Autodesk Fusion 360 part; units mm, degrees
(part 11 of 18)
  line L8111 (182.677, -216.38) -> (182.093, -216.4)
  line L8112 (99.4411, -200.179) -> (98.954, -199.84)
  line L8113 (189.133, -201.837) -> (188.753, -201.381)
  line L8114 (85.9088, -203.679) -> (85.6834, -204.229)
  line L8115 (186.561, -215.211) -> (186.044, -215.484)
  line L8116 (88.8893, -200.051) -> (88.417, -200.41)
  line L8117 (103.032, -207.35) -> (103.012, -206.757)
  line L8118 (102.594, -210.117) -> (102.758, -209.547)
  line L8119 (190.719, -205.002) -> (190.544, -204.435)
  line L8120 (101.801, -202.818) -> (101.483, -202.317)
  line L8121 (173.061, -208.139) -> (173.029, -207.555)
  line L8122 (185.918, -199.261) -> (185.373, -199.024)
  line L8123 (190.781, -209.829) -> (190.602, -210.386)
  line L8124 (100.753, -201.381) -> (100.342, -200.952)
  line L8125 (174.402, -202.554) -> (174.727, -202.069)
  line L8126 (190.827, -205.038) -> (190.957, -205.608)
  line L8127 (189.544, -212.463) -> (189.199, -212.934)
  line L8128 (183.835, -216.228) -> (183.258, -216.323)
  line L8129 (190.953, -206.166) -> (190.855, -205.58)
  line L8130 (191.125, -207.524) -> (191.095, -208.107)
  line L8131 (174.888, -212.689) -> (175.257, -213.154)
  line L8132 (85.1587, -206.538) -> (85.1245, -207.131)
  line L8133 (174.108, -203.06) -> (174.402, -202.554)
  line L8134 (184.814, -198.824) -> (184.243, -198.661)
  line L8135 (103.012, -206.757) -> (102.953, -206.166)
  line L8136 (190.855, -205.58) -> (190.719, -205.002)
  line L8137 (181.099, -198.353) -> (181.682, -198.309)
  line L8138 (173.739, -210.617) -> (173.974, -211.163)
  line L8139 (175.084, -201.606) -> (175.469, -201.166)
  line L8140 (88.417, -200.41) -> (87.9695, -200.801)
  line L8141 (101.57, -212.253) -> (101.879, -211.746)
  line L8142 (185.373, -199.024) -> (184.814, -198.824)
  line L8143 (176.783, -200.01) -> (177.268, -199.684)
  line L8144 (173.258, -208.905) -> (173.38, -209.486)
  line L8145 (188.938, -201.449) -> (189.304, -201.904)
  line L8146 (190.14, -211.459) -> (189.858, -211.97)
  line L8147 (86.466, -202.631) -> (86.17, -203.146)
  line L8148 (102.855, -205.58) -> (102.719, -205.002)
  line L8149 (173.277, -205.237) -> (173.432, -204.674)
  line L8150 (187.904, -200.551) -> (187.441, -200.179)
  line L8151 (175.469, -201.166) -> (175.882, -200.753)
  line L8152 (186.044, -215.484) -> (185.511, -215.723)
  line L8153 (186.446, -199.533) -> (185.918, -199.261)
  line L8154 (174.245, -211.691) -> (174.55, -212.201)
  line L8155 (97.9179, -199.261) -> (97.3734, -199.024)
  line L8156 (103.021, -207.787) -> (103.032, -207.35)
  line L8157 (176.643, -214.587) -> (176.187, -214.221)
  line L8158 (102.953, -206.166) -> (102.855, -205.58)
  line L8159 (173.131, -208.719) -> (173.061, -208.139)
  line L8160 (191.012, -206.757) -> (190.953, -206.166)
  line L8161 (177.121, -214.923) -> (176.643, -214.587)
  line L8162 (85.6834, -204.229) -> (85.495, -204.792)
  line L8163 (174.028, -211.487) -> (173.777, -210.959)
  line L8164 (102.544, -204.435) -> (102.332, -203.88)
  line L8165 (87.9695, -200.801) -> (87.5489, -201.22)
  line L8166 (187.673, -200.238) -> (188.121, -200.614)
  line L8167 (188.121, -200.614) -> (188.543, -201.018)
  line L8168 (177.268, -199.684) -> (177.772, -199.389)
  line L8169 (185.128, -198.83) -> (185.671, -199.044)
  line L8170 (180.276, -216.122) -> (180.861, -216.222)
  line L8171 (184.005, -198.508) -> (184.571, -198.651)
  line L8172 (190.391, -210.676) -> (190.594, -210.117)
  line L8173 (174.55, -212.201) -> (174.888, -212.689)
  line L8174 (173.622, -204.122) -> (173.848, -203.583)
  line L8175 (188.543, -201.018) -> (188.938, -201.449)
  line L8176 (186.059, -215.371) -> (186.581, -215.09)
  line L8177 (176.085, -214.005) -> (176.539, -214.387)
  line L8178 (181.509, -216.382) -> (180.927, -216.327)
  line L8179 (92.7068, -198.5) -> (92.1233, -198.611)
  line L8180 (182.093, -216.4) -> (181.509, -216.382)
  line L8181 (188.823, -213.382) -> (188.42, -213.805)
  line L8182 (92.1233, -198.611) -> (91.5484, -198.759)
  line L8183 (188.022, -214.047) -> (188.453, -213.638)
  line L8184 (180.521, -198.435) -> (181.099, -198.353)
  line L8185 (187.059, -214.905) -> (186.561, -215.211)
  line L8186 (182.483, -198.404) -> (181.889, -198.397)
  line L8187 (85.1245, -207.131) -> (85.1297, -207.725)
  line L8188 (185.671, -199.044) -> (186.199, -199.294)
  line L8189 (188.856, -213.201) -> (189.229, -212.739)
  line L8190 (181.889, -198.397) -> (181.296, -198.429)
  line L8191 (94.483, -198.404) -> (93.8893, -198.397)
  line L8192 (190.594, -210.117) -> (190.758, -209.547)
  line L8193 (175.756, -213.827) -> (175.351, -213.406)
  line L8194 (95.6626, -198.537) -> (95.075, -198.451)
  line L8195 (89.3845, -199.723) -> (88.8893, -200.051)
  line L8196 (173.035, -206.971) -> (173.078, -206.388)
  line L8197 (174.727, -202.069) -> (175.084, -201.606)
  line L8198 (100.856, -213.201) -> (101.229, -212.739)
  line L8199 (177.772, -199.389) -> (178.295, -199.128)
  line L8200 (175.882, -200.753) -> (176.32, -200.367)
  line L8201 (189.858, -211.97) -> (189.544, -212.463)
  line L8202 (178.672, -215.735) -> (178.138, -215.498)
  line L8203 (187.536, -214.568) -> (187.059, -214.905)
  line L8204 (185.511, -215.723) -> (184.963, -215.927)
  line L8205 (183.258, -216.323) -> (182.677, -216.38)
  line L8206 (96.8143, -198.824) -> (96.2432, -198.661)
  line L8207 (191.021, -207.787) -> (191.032, -207.35)
  line L8208 (173.562, -210.416) -> (173.382, -209.86)
  line L8209 (174.627, -212.489) -> (174.311, -211.998)
  line L8210 (173.848, -203.583) -> (174.108, -203.06)
  line L8211 (98.4456, -199.533) -> (97.9179, -199.261)
  line L8212 (173.432, -204.674) -> (173.622, -204.122)
  line L8213 (191.051, -206.184) -> (191.108, -206.766)
  line L8214 (102.885, -208.967) -> (102.972, -208.379)
  line L8215 (183.816, -216.134) -> (184.395, -216)
  line L8216 (174.975, -212.959) -> (174.627, -212.489)
  line L8217 (190.389, -210.93) -> (190.14, -211.459)
  line L8218 (99.9045, -200.551) -> (99.4411, -200.179)
  line L8219 (173.033, -207.131) -> (173.035, -206.971)
  line L8220 (99.5654, -214.426) -> (100.022, -214.047)
  line L8221 (97.3734, -199.024) -> (96.8143, -198.824)
  line L8222 (176.32, -200.367) -> (176.783, -200.01)
  line L8223 (86.7955, -202.137) -> (86.466, -202.631)
  line L8224 (173.238, -209.293) -> (173.131, -208.719)
  line L8225 (86.17, -203.146) -> (85.9088, -203.679)
  line L8226 (188.342, -200.952) -> (187.904, -200.551)
  line L8227 (179.22, -215.937) -> (178.672, -215.735)
  line L8228 (187.99, -214.201) -> (187.536, -214.568)
  line L8229 (180.123, -198.611) -> (179.548, -198.759)
  line L8230 (89.9003, -199.429) -> (89.3845, -199.723)
  line L8231 (173.078, -206.388) -> (173.159, -205.81)
  line L8232 (182.639, -216.287) -> (183.23, -216.23)
  line L8233 (190.456, -203.931) -> (190.659, -204.478)
  line L8234 (180.927, -216.327) -> (180.35, -216.234)
  line L8235 (183.23, -216.23) -> (183.816, -216.134)
  line L8236 (191.095, -208.107) -> (191.027, -208.688)
  line L8237 (179.132, -215.807) -> (179.699, -215.983)
  line L8238 (173.38, -209.486) -> (173.541, -210.058)
  line L8239 (101.229, -212.739) -> (101.57, -212.253)
  line L8240 (183.43, -198.402) -> (184.005, -198.508)
  line L8241 (189.879, -211.746) -> (190.153, -211.219)
  line L8242 (190.084, -203.34) -> (189.801, -202.818)
  line L8243 (93.8893, -198.397) -> (93.2963, -198.429)
  line L8244 (176.539, -214.387) -> (177.018, -214.739)
  line L8245 (191.127, -207.35) -> (191.125, -207.524)
  line L8246 (189.483, -202.317) -> (189.133, -201.837)
  line L8247 (184.395, -216) -> (184.963, -215.827)
  line L8248 (175.257, -213.154) -> (175.657, -213.593)
  line L8249 (187.084, -214.774) -> (187.565, -214.426)
  line L8250 (184.963, -215.927) -> (184.404, -216.096)
  line L8251 (90.4345, -199.169) -> (89.9003, -199.429)
  line L8252 (190.972, -208.379) -> (191.021, -207.787)
  line L8253 (190.758, -209.547) -> (190.885, -208.967)
  line L8254 (189.304, -201.904) -> (189.641, -202.381)
  line L8255 (177.9, -199.429) -> (177.385, -199.723)
  line L8256 (173.777, -210.959) -> (173.562, -210.416)
  line L8257 (186.199, -199.294) -> (186.711, -199.576)
  line L8258 (181.682, -198.309) -> (182.266, -198.302)
  line L8259 (183.663, -198.537) -> (183.075, -198.451)
  line L8260 (184.571, -198.651) -> (185.128, -198.83)
  line L8261 (98.954, -199.84) -> (98.4456, -199.533)
  line L8262 (191.027, -208.688) -> (190.922, -209.262)
  line L8263 (189.946, -202.88) -> (190.218, -203.397)
  line L8264 (102.758, -209.547) -> (102.885, -208.967)
  line L8265 (190.153, -211.219) -> (190.391, -210.676)
  line L8266 (177.385, -199.723) -> (176.889, -200.051)
  line L8267 (189.641, -202.381) -> (189.946, -202.88)
  line L8268 (102.084, -203.34) -> (101.801, -202.818)
  line L8269 (187.441, -200.179) -> (186.954, -199.84)
  line L8270 (173.174, -208.317) -> (173.258, -208.905)
  line L8271 (182.85, -198.333) -> (183.43, -198.402)
  line L8272 (189.229, -212.739) -> (189.57, -212.253)
  line L8273 (191.108, -206.766) -> (191.127, -207.35)
  line L8274 (188.753, -201.381) -> (188.342, -200.952)
  line L8275 (90.9847, -198.946) -> (90.4345, -199.169)
  line L8276 (93.2963, -198.429) -> (92.7068, -198.5)
  line L8277 (189.199, -212.934) -> (188.823, -213.382)
  line L8278 (176.187, -214.221) -> (175.756, -213.827)
  line L8279 (179.386, -198.709) -> (179.949, -198.554)
  line L8280 (173.541, -210.058) -> (173.739, -210.617)
  line L8281 (190.885, -208.967) -> (190.972, -208.379)
  line L8282 (186.954, -199.84) -> (186.446, -199.533)
  line L8283 (95.075, -198.451) -> (94.483, -198.404)
  line L8284 (190.659, -204.478) -> (190.827, -205.038)
  line L8285 (102.972, -208.379) -> (103.021, -207.787)
  line L8286 (173.382, -209.86) -> (173.238, -209.293)
  line L8287 (187.203, -199.892) -> (187.673, -200.238)
  line L8288 (179.949, -198.554) -> (180.521, -198.435)
  line L8289 (87.5489, -201.22) -> (87.157, -201.666)
  line L8290 (102.391, -210.676) -> (102.594, -210.117)
  line L8291 (181.452, -216.283) -> (182.046, -216.305)
  line L8292 (102.719, -205.002) -> (102.544, -204.435)
  line L8293 (85.2321, -205.949) -> (85.1587, -206.538)
  line L8294 (101.133, -201.837) -> (100.753, -201.381)
  line L8295 (181.296, -198.429) -> (180.707, -198.5)
  line L8296 (184.243, -198.661) -> (183.663, -198.537)
  line L8297 (179.78, -216.104) -> (179.22, -215.937)
  line L8298 (190.218, -203.397) -> (190.456, -203.931)
  line L8299 (174.311, -211.998) -> (174.028, -211.487)
  line L8300 (177.018, -214.739) -> (177.518, -215.058)
  line L8301 (180.861, -216.222) -> (181.452, -216.283)
  line L8302 (179.548, -198.759) -> (178.985, -198.946)
  line L8303 (180.707, -198.5) -> (180.123, -198.611)
  line L8304 (175.657, -213.593) -> (176.085, -214.005)
  line L8305 (178.434, -199.169) -> (177.9, -199.429)
  line L8306 (176.417, -200.41) -> (175.97, -200.801)
  line L8307 (177.62, -215.227) -> (177.121, -214.923)
  line L8308 (102.153, -211.219) -> (102.391, -210.676)
  line L8309 (185.518, -215.617) -> (186.059, -215.371)
  line L8310 (100.342, -200.952) -> (99.9045, -200.551)
  line L8311 (182.266, -198.302) -> (182.85, -198.333)
  line L8312 (180.35, -216.234) -> (179.78, -216.104)
  line L8313 (176.889, -200.051) -> (176.417, -200.41)
  line L8314 (101.879, -211.746) -> (102.153, -211.219)
  line L8315 (178.039, -215.343) -> (178.578, -215.593)
  line L8316 (173.159, -205.81) -> (173.277, -205.237)
  line L8317 (178.138, -215.498) -> (177.62, -215.227)
  line L8318 (188.42, -213.805) -> (187.99, -214.201)
  line L8319 (173.029, -207.555) -> (173.033, -207.131)
  line L8320 (186.711, -199.576) -> (187.203, -199.892)
  line L8321 (178.985, -198.946) -> (178.434, -199.169)
  line L8322 (183.075, -198.451) -> (182.483, -198.404)
  line L8323 (101.483, -202.317) -> (101.133, -201.837)
  line L8324 (179.699, -215.983) -> (180.276, -216.122)
  line L8325 (91.5484, -198.759) -> (90.9847, -198.946)
  line L8326 (178.834, -198.901) -> (179.386, -198.709)
  line L8327 (184.404, -216.096) -> (183.835, -216.228)
  line L8328 (182.483, -174.704) -> (181.889, -174.697)
  line L8329 (153.549, -201.22) -> (153.157, -201.666)
  line L8330 (151.344, -181.666) -> (151.232, -182.249)
  line L8331 (180.861, -192.522) -> (181.452, -192.583)
  line L8332 (162.395, -192.3) -> (162.963, -192.127)
  line L8333 (187.441, -176.479) -> (186.954, -176.14)
  line L8334 (53.1275, -198.83) -> (53.671, -199.044)
  line L8335 (187.203, -176.192) -> (187.673, -176.538)
  line L8336 (155.385, -199.723) -> (154.889, -200.051)
  line L8337 (175.882, -177.053) -> (176.32, -176.667)
  line L8338 (169.032, -183.65) -> (169.012, -183.057)
  line L8339 (186.711, -175.876) -> (187.203, -176.192)
  line L8340 (164.954, -176.14) -> (164.446, -175.833)
  line L8341 (168.719, -181.302) -> (168.544, -180.735)
  line L8342 (190.855, -181.88) -> (190.719, -181.302)
  line L8343 (176.539, -190.687) -> (177.018, -191.039)
  line L8344 (173.078, -182.688) -> (173.159, -182.11)
  line L8345 (173.061, -184.439) -> (173.029, -183.855)
  line L8346 (169.032, -207.35) -> (169.012, -206.757)
  line L8347 (190.719, -181.302) -> (190.544, -180.735)
  line L8348 (188.823, -189.682) -> (188.42, -190.105)
  line L8349 (191.032, -183.65) -> (191.012, -183.057)
  line L8350 (179.386, -175.009) -> (179.949, -174.854)
  line L8351 (181.889, -174.697) -> (181.296, -174.729)
  line L8352 (188.121, -176.914) -> (188.543, -177.318)
  line L8353 (47.9488, -198.554) -> (48.5208, -198.435)
  line L8354 (156.985, -198.946) -> (156.434, -199.169)
  line L8355 (190.659, -180.778) -> (190.827, -181.338)
  line L8356 (163.373, -175.324) -> (162.814, -175.124)
  line L8357 (112.834, -175.201) -> (113.386, -175.009)
  line L8358 (189.801, -179.118) -> (189.483, -178.617)
  line L8359 (175.469, -177.466) -> (175.882, -177.053)
  line L8360 (154.889, -200.051) -> (154.417, -200.41)
  line L8361 (190.456, -180.231) -> (190.659, -180.778)
  line L8362 (185.918, -175.561) -> (185.373, -175.324)
  line L8363 (123.946, -179.18) -> (124.218, -179.697)
  line L8364 (173.159, -182.11) -> (173.277, -181.537)
  line L8365 (183.43, -174.702) -> (184.005, -174.808)
  line L8366 (42.402, -202.554) -> (42.7274, -202.069)
  line L8367 (168.084, -203.34) -> (167.801, -202.818)
  line L8368 (188.342, -177.252) -> (187.904, -176.851)
  line L8369 (188.022, -190.347) -> (188.453, -189.938)
  line L8370 (183.816, -192.434) -> (184.395, -192.3)
  line L8371 (116.266, -174.602) -> (116.85, -174.633)
  line L8372 (108.727, -178.369) -> (109.084, -177.906)
  line L8373 (121.203, -176.192) -> (121.673, -176.538)
  line L8374 (178.578, -191.893) -> (179.132, -192.107)
  line L8375 (189.229, -189.039) -> (189.57, -188.553)
  line L8376 (152.795, -202.137) -> (152.466, -202.631)
  line L8377 (49.0994, -198.353) -> (49.682, -198.309)
  line L8378 (41.078, -206.388) -> (41.1589, -205.81)
  line L8379 (190.972, -184.679) -> (191.021, -184.087)
  line L8380 (173.258, -185.205) -> (173.38, -185.786)
  line L8381 (177.772, -175.689) -> (178.295, -175.428)
  line L8382 (187.536, -190.868) -> (187.059, -191.205)
  line L8383 (191.021, -184.087) -> (191.032, -183.65)
  line L8384 (180.123, -174.911) -> (179.548, -175.059)
  line L8385 (186.044, -191.784) -> (185.511, -192.023)
  line L8386 (152.466, -178.931) -> (152.17, -179.446)
  line L8387 (173.38, -185.786) -> (173.541, -186.358)
  line L8388 (177.018, -191.039) -> (177.518, -191.358)
  line L8389 (108.402, -178.854) -> (108.727, -178.369)
  line L8390 (182.85, -174.633) -> (183.43, -174.702)
  line L8391 (184.963, -192.227) -> (184.404, -192.396)
  line L8392 (178.138, -191.798) -> (177.62, -191.527)
  line L8393 (184.243, -174.961) -> (183.663, -174.837)
  line L8394 (173.277, -181.537) -> (173.432, -180.974)
  line L8395 (168.758, -209.547) -> (168.885, -208.967)
  line L8396 (154.417, -176.71) -> (153.97, -177.101)
  line L8397 (168.332, -180.18) -> (168.084, -179.64)
  line L8398 (191.027, -184.988) -> (190.922, -185.562)
  line L8399 (53.671, -199.044) -> (54.1995, -199.294)
  line L8400 (189.946, -179.18) -> (190.218, -179.697)
  line L8401 (185.373, -175.324) -> (184.814, -175.124)
  line L8402 (180.927, -192.627) -> (180.35, -192.534)
  line L8403 (109.469, -177.466) -> (109.882, -177.053)
  line L8404 (189.858, -188.27) -> (189.544, -188.763)
  line L8405 (174.627, -188.789) -> (174.311, -188.298)
  line L8406 (152.466, -202.631) -> (152.17, -203.146)
  line L8407 (107.078, -182.688) -> (107.159, -182.11)
  line L8408 (187.059, -191.205) -> (186.561, -191.511)
  line L8409 (173.541, -186.358) -> (173.739, -186.917)
  line L8410 (163.518, -191.917) -> (164.059, -191.671)
  line L8411 (153.97, -177.101) -> (153.549, -177.52)
  line L8412 (167.483, -178.617) -> (167.133, -178.137)
  line L8413 (173.131, -185.019) -> (173.061, -184.439)
  line L8414 (185.511, -192.023) -> (184.963, -192.227)
  line L8415 (52.0047, -198.508) -> (52.5713, -198.651)
  line L8416 (173.848, -179.883) -> (174.108, -179.36)
  line L8417 (151.232, -205.949) -> (151.159, -206.538)
  line L8418 (168.594, -186.417) -> (168.758, -185.847)
  line L8419 (166.753, -177.681) -> (166.342, -177.252)
  line L8420 (188.938, -177.749) -> (189.304, -178.204)
  line L8421 (42.7274, -202.069) -> (43.0836, -201.606)
  line L8422 (163.373, -199.024) -> (162.814, -198.824)
  line L8423 (124.602, -186.686) -> (124.389, -187.23)
  line L8424 (190.957, -181.908) -> (191.051, -182.484)
  line L8425 (165.565, -190.726) -> (166.022, -190.347)
  line L8426 (173.909, -179.979) -> (173.683, -180.529)
  line L8427 (123.304, -178.204) -> (123.641, -178.681)
  line L8428 (179.132, -192.107) -> (179.699, -192.283)
  line L8429 (164.059, -191.671) -> (164.581, -191.39)
  line L8430 (174.245, -187.991) -> (174.55, -188.501)
  line L8431 (189.483, -178.617) -> (189.133, -178.137)
  line L8432 (180.35, -192.534) -> (179.78, -192.404)
  line L8433 (153.157, -201.666) -> (152.795, -202.137)
  line L8434 (45.7724, -199.389) -> (46.2951, -199.128)
  line L8435 (46.8336, -198.901) -> (47.3856, -198.709)
  line L8436 (191.051, -182.484) -> (191.108, -183.066)
  line L8437 (111.268, -175.984) -> (111.772, -175.689)
  line L8438 (158.276, -192.422) -> (158.861, -192.522)
  line L8439 (122.543, -177.318) -> (122.938, -177.749)
  line L8440 (124.659, -180.778) -> (124.827, -181.338)
  line L8441 (188.753, -177.681) -> (188.342, -177.252)
  line L8442 (168.391, -186.976) -> (168.594, -186.417)
  line L8443 (151.909, -203.679) -> (151.683, -204.229)
  line L8444 (159.452, -192.583) -> (160.046, -192.605)
  line L8445 (168.972, -184.679) -> (169.021, -184.087)
  line L8446 (152.795, -178.437) -> (152.466, -178.931)
  line L8447 (180.521, -174.735) -> (181.099, -174.653)
  line L8448 (190.885, -185.267) -> (190.972, -184.679)
  line L8449 (173.035, -183.271) -> (173.078, -182.688)
  line L8450 (189.544, -188.763) -> (189.199, -189.234)
  line L8451 (181.296, -174.729) -> (180.707, -174.8)
  line L8452 (151.124, -183.431) -> (151.13, -184.025)
  line L8453 (114.521, -174.735) -> (115.099, -174.653)
  line L8454 (184.005, -174.808) -> (184.571, -174.951)
  line L8455 (182.639, -192.587) -> (183.23, -192.53)
  line L8456 (41.8482, -203.583) -> (42.1085, -203.06)
  line L8457 (156.985, -175.246) -> (156.434, -175.469)
  line L8458 (167.483, -202.317) -> (167.133, -201.837)
  line L8459 (174.311, -188.298) -> (174.028, -187.787)
  line L8460 (179.78, -192.404) -> (179.22, -192.237)
  line L8461 (41.2769, -205.237) -> (41.4315, -204.674)
  line L8462 (173.238, -185.593) -> (173.131, -185.019)
  line L8463 (173.13, -184.025) -> (173.174, -184.617)
  line L8464 (177.518, -191.358) -> (178.039, -191.643)
  line L8465 (190.781, -186.129) -> (190.602, -186.686)
  line L8466 (168.544, -180.735) -> (168.332, -180.18)
  line L8467 (50.8498, -198.333) -> (51.4301, -198.402)
  line L8468 (124.957, -181.908) -> (125.051, -182.484)
  line L8469 (109.084, -177.906) -> (109.469, -177.466)
  line L8470 (113.386, -175.009) -> (113.949, -174.854)
  line L8471 (165.904, -200.551) -> (165.441, -200.179)
  line L8472 (168.855, -181.88) -> (168.719, -181.302)
  line L8473 (179.548, -175.059) -> (178.985, -175.246)
  line L8474 (122.121, -176.914) -> (122.543, -177.318)
  line L8475 (43.8816, -200.753) -> (44.3203, -200.367)
  line L8476 (124.218, -179.697) -> (124.456, -180.231)
  line L8477 (159.889, -198.397) -> (159.296, -198.429)
  line L8478 (156.578, -191.893) -> (157.132, -192.107)
  line L8479 (188.42, -190.105) -> (187.99, -190.501)
  line L8480 (151.13, -207.725) -> (151.174, -208.317)
  line L8481 (163.918, -175.561) -> (163.373, -175.324)
  line L8482 (174.975, -189.259) -> (174.627, -188.789)
  line L8483 (118.571, -174.951) -> (119.128, -175.13)
  line L8484 (156.434, -175.469) -> (155.9, -175.729)
  line L8485 (124.781, -186.129) -> (124.602, -186.686)
  line L8486 (159.296, -198.429) -> (158.707, -198.5)
  line L8487 (189.199, -189.234) -> (188.823, -189.682)
  line L8488 (119.128, -175.13) -> (119.671, -175.344)
  line L8489 (175.351, -189.706) -> (174.975, -189.259)
  line L8490 (151.159, -206.538) -> (151.124, -207.131)
  line L8491 (173.382, -186.16) -> (173.238, -185.593)
  line L8492 (173.344, -181.666) -> (173.232, -182.249)
  line L8493 (174.888, -188.989) -> (175.257, -189.454)
  line L8494 (125.095, -184.407) -> (125.027, -184.988)
  line L8495 (167.229, -189.039) -> (167.57, -188.553)
  line L8496 (44.3203, -200.367) -> (44.7829, -200.01)
  line L8497 (168.084, -179.64) -> (167.801, -179.118)
  line L8498 (165.084, -191.074) -> (165.565, -190.726)
  line L8499 (158.123, -198.611) -> (157.548, -198.759)
  line L8500 (178.434, -175.469) -> (177.9, -175.729)
  line L8501 (169.021, -207.787) -> (169.032, -207.35)
  line L8502 (108.108, -179.36) -> (108.402, -178.854)
  line L8503 (168.953, -182.466) -> (168.855, -181.88)
  line L8504 (120.711, -175.876) -> (121.203, -176.192)
  line L8505 (190.594, -186.417) -> (190.758, -185.847)
  line L8506 (165.441, -176.479) -> (164.954, -176.14)
  line L8507 (112.295, -175.428) -> (112.834, -175.201)
  line L8508 (179.949, -174.854) -> (180.521, -174.735)
  line L8509 (155.385, -176.023) -> (154.889, -176.351)
  line L8510 (191.012, -183.057) -> (190.953, -182.466)
  line L8511 (42.1085, -203.06) -> (42.402, -202.554)
  line L8512 (158.123, -174.911) -> (157.548, -175.059)
  line L8513 (157.548, -198.759) -> (156.985, -198.946)
  line L8514 (107.432, -180.974) -> (107.622, -180.422)
  line L8515 (185.128, -175.13) -> (185.671, -175.344)
  line L8516 (173.974, -187.463) -> (174.245, -187.991)
  line L8517 (41.6223, -204.122) -> (41.8482, -203.583)
  line L8518 (189.133, -178.137) -> (188.753, -177.681)
  line L8519 (125.027, -184.988) -> (124.922, -185.562)
  line L8520 (179.22, -192.237) -> (178.672, -192.035)
  line L8521 (161.075, -198.451) -> (160.483, -198.404)
  line L8522 (190.389, -187.23) -> (190.14, -187.759)
  line L8523 (188.543, -177.318) -> (188.938, -177.749)
  line L8524 (187.084, -191.074) -> (187.565, -190.726)
  line L8525 (151.683, -180.529) -> (151.495, -181.092)
  line L8526 (153.549, -177.52) -> (153.157, -177.966)
  line L8527 (184.404, -192.396) -> (183.835, -192.528)
  line L8528 (186.199, -175.594) -> (186.711, -175.876)
  line L8529 (159.296, -174.729) -> (158.707, -174.8)
  line L8530 (184.963, -192.127) -> (185.518, -191.917)
  line L8531 (166.342, -177.252) -> (165.904, -176.851)
  line L8532 (155.9, -175.729) -> (155.385, -176.023)
  line L8533 (174.795, -178.437) -> (174.466, -178.931)
  line L8534 (187.565, -190.726) -> (188.022, -190.347)
  line L8535 (153.97, -200.801) -> (153.549, -201.22)
  line L8536 (167.133, -178.137) -> (166.753, -177.681)
  line L8537 (41.1589, -205.81) -> (41.2769, -205.237)
  line L8538 (191.095, -184.407) -> (191.027, -184.988)
  line L8539 (125.051, -182.484) -> (125.108, -183.066)
  line L8540 (175.549, -177.52) -> (175.157, -177.966)
  line L8541 (161.816, -192.434) -> (162.395, -192.3)
  line L8542 (161.663, -174.837) -> (161.075, -174.751)
  line L8543 (151.683, -204.229) -> (151.495, -204.792)
  line L8544 (113.949, -174.854) -> (114.521, -174.735)
  line L8545 (162.243, -174.961) -> (161.663, -174.837)
  line L8546 (177.268, -175.984) -> (177.772, -175.689)
  line L8547 (173.683, -180.529) -> (173.495, -181.092)
  line L8548 (185.518, -191.917) -> (186.059, -191.671)
  line L8549 (107.622, -180.422) -> (107.848, -179.883)
  line L8550 (176.085, -190.305) -> (176.539, -190.687)
  line L8551 (167.133, -201.837) -> (166.753, -201.381)
  line L8552 (125.127, -183.65) -> (125.125, -183.824)
  line L8553 (52.5713, -198.651) -> (53.1275, -198.83)
  line L8554 (120.199, -175.594) -> (120.711, -175.876)
  line L8555 (125.108, -183.066) -> (125.127, -183.65)
  line L8556 (51.4301, -198.402) -> (52.0047, -198.508)
  line L8557 (175.756, -190.127) -> (175.351, -189.706)
  line L8558 (168.885, -185.267) -> (168.972, -184.679)
  line L8559 (166.856, -189.501) -> (167.229, -189.039)
  line L8560 (181.682, -174.609) -> (182.266, -174.602)
  line L8561 (124.389, -187.23) -> (124.14, -187.759)
  line L8562 (181.099, -174.653) -> (181.682, -174.609)
  line L8563 (186.059, -191.671) -> (186.581, -191.39)
  line L8564 (178.039, -191.643) -> (178.578, -191.893)
  line L8565 (184.571, -174.951) -> (185.128, -175.13)
  line L8566 (161.23, -192.53) -> (161.816, -192.434)
  line L8567 (167.801, -179.118) -> (167.483, -178.617)
  line L8568 (165.441, -200.179) -> (164.954, -199.84)
  line L8569 (169.021, -184.087) -> (169.032, -183.65)
  line L8570 (189.641, -178.681) -> (189.946, -179.18)
  line L8571 (123.641, -178.681) -> (123.946, -179.18)
  line L8572 (160.483, -174.704) -> (159.889, -174.697)
  line L8573 (168.544, -204.435) -> (168.332, -203.88)
  line L8574 (166.453, -189.938) -> (166.856, -189.501)
  line L8575 (163.918, -199.261) -> (163.373, -199.024)
  line L8576 (166.753, -201.381) -> (166.342, -200.952)
  line L8577 (190.922, -185.562) -> (190.781, -186.129)
  line L8578 (159.889, -174.697) -> (159.296, -174.729)
  line L8579 (190.758, -185.847) -> (190.885, -185.267)
  line L8580 (151.495, -181.092) -> (151.344, -181.666)
  line L8581 (176.643, -190.887) -> (176.187, -190.521)
  line L8582 (124.827, -181.338) -> (124.957, -181.908)
  line L8583 (177.9, -175.729) -> (177.385, -176.023)
  line L8584 (173.033, -183.431) -> (173.035, -183.271)
  line L8585 (174.466, -178.931) -> (174.17, -179.446)
  line L8586 (175.97, -177.101) -> (175.549, -177.52)
  line L8587 (155.9, -199.429) -> (155.385, -199.723)
  line L8588 (151.909, -179.979) -> (151.683, -180.529)
  line L8589 (168.855, -205.58) -> (168.719, -205.002)
  line L8590 (183.835, -192.528) -> (183.258, -192.623)
  line L8591 (177.385, -176.023) -> (176.889, -176.351)
  line L8592 (153.157, -177.966) -> (152.795, -178.437)
  line L8593 (190.332, -180.18) -> (190.084, -179.64)
  line L8594 (158.861, -192.522) -> (159.452, -192.583)
  line L8595 (119.671, -175.344) -> (120.199, -175.594)
  line L8596 (175.657, -189.893) -> (176.085, -190.305)
  line L8597 (176.187, -190.521) -> (175.756, -190.127)
  line L8598 (116.85, -174.633) -> (117.43, -174.702)
  line L8599 (111.772, -175.689) -> (112.295, -175.428)
  line L8600 (178.295, -175.428) -> (178.834, -175.201)
  line L8601 (174.402, -178.854) -> (174.727, -178.369)
  line L8602 (168.953, -206.166) -> (168.855, -205.58)
  line L8603 (115.682, -174.609) -> (116.266, -174.602)
  line L8604 (173.622, -180.422) -> (173.848, -179.883)
  line L8605 (152.17, -179.446) -> (151.909, -179.979)
  line L8606 (107.159, -182.11) -> (107.277, -181.537)
  line L8607 (110.32, -176.667) -> (110.783, -176.31)
  line L8608 (190.602, -186.686) -> (190.389, -187.23)
  line L8609 (174.028, -187.787) -> (173.777, -187.259)
  line L8610 (49.682, -198.309) -> (50.2663, -198.302)
  line L8611 (182.677, -192.68) -> (182.093, -192.7)
  line L8612 (151.344, -205.366) -> (151.232, -205.949)
  line L8613 (175.157, -177.966) -> (174.795, -178.437)
  line L8614 (178.834, -175.201) -> (179.386, -175.009)
  line L8615 (186.561, -191.511) -> (186.044, -191.784)
  line L8616 (164.954, -199.84) -> (164.446, -199.533)
  line L8617 (157.132, -192.107) -> (157.699, -192.283)
  line L8618 (167.879, -188.046) -> (168.153, -187.519)
  line L8619 (191.108, -183.066) -> (191.127, -183.65)
  line L8620 (176.32, -176.667) -> (176.783, -176.31)
  line L8621 (180.707, -174.8) -> (180.123, -174.911)
  line L8622 (162.814, -175.124) -> (162.243, -174.961)
  line L8623 (162.243, -198.661) -> (161.663, -198.537)
  line L8624 (173.562, -186.716) -> (173.382, -186.16)
  line L8625 (190.084, -179.64) -> (189.801, -179.118)
  line L8626 (184.395, -192.3) -> (184.963, -192.127)
  line L8627 (117.43, -174.702) -> (118.005, -174.808)
  line L8628 (187.904, -176.851) -> (187.441, -176.479)
  line L8629 (161.075, -174.751) -> (160.483, -174.704)
  line L8630 (189.879, -188.046) -> (190.153, -187.519)
  line L8631 (154.889, -176.351) -> (154.417, -176.71)
  line L8632 (190.544, -180.735) -> (190.332, -180.18)
  line L8633 (177.62, -191.527) -> (177.121, -191.223)
  line L8634 (184.814, -175.124) -> (184.243, -174.961)
  line L8635 (167.801, -202.818) -> (167.483, -202.317)
  line L8636 (173.777, -187.259) -> (173.562, -186.716)
  line L8637 (168.885, -208.967) -> (168.972, -208.379)
  line L8638 (152.17, -203.146) -> (151.909, -203.679)
  line L8639 (168.153, -187.519) -> (168.391, -186.976)
  line L8640 (167.57, -188.553) -> (167.879, -188.046)
  line L8641 (188.453, -189.938) -> (188.856, -189.501)
  line L8642 (166.342, -200.952) -> (165.904, -200.551)
  line L8643 (156.039, -191.643) -> (156.578, -191.893)
  line L8644 (115.099, -174.653) -> (115.682, -174.609)
  line L8645 (185.671, -175.344) -> (186.199, -175.594)
  line L8646 (173.174, -184.617) -> (173.258, -185.205)
  line L8647 (187.673, -176.538) -> (188.121, -176.914)
  line L8648 (173.739, -186.917) -> (173.974, -187.463)
  line L8649 (156.434, -199.169) -> (155.9, -199.429)
  line L8650 (44.7829, -200.01) -> (45.2676, -199.684)
  line L8651 (173.495, -181.092) -> (173.344, -181.666)
  line L8652 (158.707, -174.8) -> (158.123, -174.911)
  line L8653 (178.672, -192.035) -> (178.138, -191.798)
  line L8654 (151.495, -204.792) -> (151.344, -205.366)
  line L8655 (173.159, -182.838) -> (173.124, -183.431)
  line L8656 (173.232, -182.249) -> (173.159, -182.838)
  line L8657 (188.856, -189.501) -> (189.229, -189.039)
  line L8658 (124.456, -180.231) -> (124.659, -180.778)
  line L8659 (47.3856, -198.709) -> (47.9488, -198.554)
  line L8660 (160.639, -192.587) -> (161.23, -192.53)
  line L8661 (158.707, -198.5) -> (158.123, -198.611)
  line L8662 (50.2663, -198.302) -> (50.8498, -198.333)
  line L8663 (177.121, -191.223) -> (176.643, -190.887)
  line L8664 (182.093, -192.7) -> (181.509, -192.682)
  line L8665 (151.232, -182.249) -> (151.159, -182.838)
  line L8666 (118.005, -174.808) -> (118.571, -174.951)
  line L8667 (151.124, -207.131) -> (151.13, -207.725)
  line L8668 (183.075, -174.751) -> (182.483, -174.704)
  line L8669 (190.14, -187.759) -> (189.858, -188.27)
  line L8670 (178.985, -175.246) -> (178.434, -175.469)
  line L8671 (183.23, -192.53) -> (183.816, -192.434)
  line L8672 (157.548, -175.059) -> (156.985, -175.246)
  line L8673 (54.1995, -199.294) -> (54.7108, -199.576)
  line L8674 (179.699, -192.283) -> (180.276, -192.422)
  line L8675 (180.276, -192.422) -> (180.861, -192.522)
  line L8676 (183.258, -192.623) -> (182.677, -192.68)
  line L8677 (186.581, -191.39) -> (187.084, -191.074)
  line L8678 (176.889, -176.351) -> (176.417, -176.71)
  line L8679 (168.719, -205.002) -> (168.544, -204.435)
  line L8680 (169.012, -183.057) -> (168.953, -182.466)
  line L8681 (181.509, -192.682) -> (180.927, -192.627)
  line L8682 (168.758, -185.847) -> (168.885, -185.267)
  line L8683 (176.783, -176.31) -> (177.268, -175.984)
  line L8684 (187.99, -190.501) -> (187.536, -190.868)
  line L8685 (181.452, -192.583) -> (182.046, -192.605)
  line L8686 (191.125, -183.824) -> (191.095, -184.407)
  line L8687 (175.257, -189.454) -> (175.657, -189.893)
  line L8688 (165.904, -176.851) -> (165.441, -176.479)
  line L8689 (45.2676, -199.684) -> (45.7724, -199.389)
  line L8690 (173.029, -183.855) -> (173.033, -183.431)
  line L8691 (166.022, -190.347) -> (166.453, -189.938)
  line L8692 (154.417, -200.41) -> (153.97, -200.801)
  line L8693 (162.963, -192.127) -> (163.518, -191.917)
  line L8694 (164.446, -199.533) -> (163.918, -199.261)
  line L8695 (162.814, -198.824) -> (162.243, -198.661)
  line L8696 (109.882, -177.053) -> (110.32, -176.667)
  line L8697 (175.084, -177.906) -> (175.469, -177.466)
  line L8698 (174.108, -179.36) -> (174.402, -178.854)
  line L8699 (164.446, -175.833) -> (163.918, -175.561)
  line L8700 (182.046, -192.605) -> (182.639, -192.587)
  line L8701 (164.581, -191.39) -> (165.084, -191.074)
  line L8702 (160.483, -198.404) -> (159.889, -198.397)
  line L8703 (107.848, -179.883) -> (108.108, -179.36)
  line L8704 (151.159, -182.838) -> (151.124, -183.431)
  line L8705 (121.673, -176.538) -> (122.121, -176.914)
  line L8706 (190.153, -187.519) -> (190.391, -186.976)
  line L8707 (110.783, -176.31) -> (111.268, -175.984)
  line L8708 (176.417, -176.71) -> (175.97, -177.101)
  line L8709 (189.57, -188.553) -> (189.879, -188.046)
  line L8710 (48.5208, -198.435) -> (49.0994, -198.353)
  line L8711 (190.827, -181.338) -> (190.957, -181.908)
  line L8712 (182.266, -174.602) -> (182.85, -174.633)
  line L8713 (41.4315, -204.674) -> (41.6223, -204.122)
  line L8714 (191.127, -183.65) -> (191.125, -183.824)
  line L8715 (46.2951, -199.128) -> (46.8336, -198.901)
  line L8716 (160.046, -192.605) -> (160.639, -192.587)
  line L8717 (168.972, -208.379) -> (169.021, -207.787)
  line L8718 (173.432, -180.974) -> (173.622, -180.422)
  line L8719 (157.699, -192.283) -> (158.276, -192.422)
  line L8720 (186.446, -175.833) -> (185.918, -175.561)
  line L8721 (189.304, -178.204) -> (189.641, -178.681)
  line L8722 (168.332, -203.88) -> (168.084, -203.34)
  line L8723 (190.391, -186.976) -> (190.594, -186.417)
  line L8724 (151.13, -184.025) -> (151.174, -184.617)
  line L8725 (190.953, -182.466) -> (190.855, -181.88)
  line L8726 (183.663, -174.837) -> (183.075, -174.751)
  line L8727 (169.012, -206.757) -> (168.953, -206.166)
  line L8728 (173.124, -183.431) -> (173.13, -184.025)
  line L8729 (124.922, -185.562) -> (124.781, -186.129)
  line L8730 (174.17, -179.446) -> (173.909, -179.979)
  line L8731 (186.954, -176.14) -> (186.446, -175.833)
  line L8732 (174.55, -188.501) -> (174.888, -188.989)
  line L8733 (54.7108, -199.576) -> (55.2028, -199.892)
  line L8734 (122.938, -177.749) -> (123.304, -178.204)
  line L8735 (43.4688, -201.166) -> (43.8816, -200.753)
  line L8736 (161.663, -198.537) -> (161.075, -198.451)
  line L8737 (43.0836, -201.606) -> (43.4688, -201.166)
  line L8738 (107.277, -181.537) -> (107.432, -180.974)
  line L8739 (190.218, -179.697) -> (190.456, -180.231)
  line L8740 (174.727, -178.369) -> (175.084, -177.906)
  line L8741 (125.125, -183.824) -> (125.095, -184.407)
  line L8742 (36.9224, -209.262) -> (36.7806, -209.829)
  line L8743 (44.1873, -214.221) -> (43.7561, -213.827)
  line L8744 (19.9741, -211.163) -> (20.2446, -211.691)
  line L8745 (32.954, -199.84) -> (32.4456, -199.533)
  line L8746 (43.7561, -213.827) -> (43.3513, -213.406)
  line L8747 (45.6204, -215.227) -> (45.1214, -214.923)
  line L8748 (45.9003, -199.429) -> (45.3845, -199.723)
  line L8749 (54.5813, -215.09) -> (55.0844, -214.774)
  line L8750 (50.0455, -216.305) -> (50.6391, -216.287)
  line L8751 (20.0276, -211.487) -> (19.7774, -210.959)
  line L8752 (26.7068, -198.5) -> (26.1233, -198.611)
  line L8753 (123.946, -202.88) -> (124.218, -203.397)
  line L8754 (107.078, -206.388) -> (107.159, -205.81)
  line L8755 (27.0994, -198.353) -> (27.682, -198.309)
  line L8756 (56.9379, -201.449) -> (57.3045, -201.904)
  line L8757 (22.0847, -214.005) -> (22.539, -214.387)
  line L8758 (36.6024, -210.386) -> (36.3887, -210.93)
  line L8759 (119.671, -199.044) -> (120.199, -199.294)
  line L8760 (57.3045, -201.904) -> (57.6409, -202.381)
  line L8761 (46.4345, -199.169) -> (45.9003, -199.429)
  line L8762 (59.1268, -207.35) -> (59.1251, -207.524)
  line L8763 (47.2202, -215.937) -> (46.672, -215.735)
  line L8764 (115.099, -198.353) -> (115.682, -198.309)
  line L8765 (21.6569, -213.593) -> (22.0847, -214.005)
  line L8766 (36.4559, -203.931) -> (36.6591, -204.478)
  line L8767 (25.3856, -198.709) -> (25.9488, -198.554)
  line L8768 (47.6987, -215.983) -> (48.2761, -216.122)
  line L8769 (107.622, -204.122) -> (107.848, -203.583)
  line L8770 (53.5182, -215.617) -> (54.0585, -215.371)
  line L8771 (41.3817, -209.86) -> (41.2379, -209.293)
  line L8772 (36.9531, -206.166) -> (36.8551, -205.58)
  line L8773 (19.2769, -205.237) -> (19.4315, -204.674)
  line L8774 (19.1297, -207.725) -> (19.1742, -208.317)
  line L8775 (48.2761, -216.122) -> (48.8615, -216.222)
  line L8776 (36.9725, -208.379) -> (37.0211, -207.787)
  line L8777 (37.0318, -207.35) -> (37.0121, -206.757)
  line L8778 (32.0441, -215.484) -> (31.5109, -215.723)
  line L8779 (20.6274, -212.489) -> (20.3113, -211.998)
  line L8780 (28.6766, -216.38) -> (28.0926, -216.4)
  line L8781 (125.051, -206.184) -> (125.108, -206.766)
  line L8782 (115.682, -198.309) -> (116.266, -198.302)
  line L8783 (34.42, -213.805) -> (33.9903, -214.201)
  line L8784 (48.7068, -198.5) -> (48.1233, -198.611)
  line L8785 (55.2028, -199.892) -> (55.6734, -200.238)
  line L8786 (35.3045, -201.904) -> (35.6409, -202.381)
  line L8787 (36.3914, -210.676) -> (36.5935, -210.117)
  line L8788 (57.4833, -202.317) -> (57.1334, -201.837)
  line L8789 (20.7955, -202.137) -> (20.466, -202.631)
  line L8790 (32.4456, -199.533) -> (31.9179, -199.261)
  line L8791 (58.1404, -211.459) -> (57.8585, -211.97)
  line L8792 (30.9627, -215.827) -> (31.5182, -215.617)
  line L8793 (51.075, -198.451) -> (50.483, -198.404)
  line L8794 (37.0211, -207.787) -> (37.0318, -207.35)
  line L8795 (36.1404, -211.459) -> (35.8585, -211.97)
  line L8796 (41.1245, -207.131) -> (41.1297, -207.725)
  line L8797 (34.453, -213.638) -> (34.8557, -213.201)
  line L8798 (122.121, -200.614) -> (122.543, -201.018)
  line L8799 (28.2663, -198.302) -> (28.8498, -198.333)
  line L8800 (59.0274, -208.688) -> (58.9224, -209.262)
  line L8801 (25.6987, -215.983) -> (26.2761, -216.122)
  line L8802 (108.727, -202.069) -> (109.084, -201.606)
  line L8803 (41.1587, -206.538) -> (41.1245, -207.131)
  line L8804 (48.8615, -216.222) -> (49.4521, -216.283)
  line L8805 (59.0121, -206.757) -> (58.9531, -206.166)
  line L8806 (48.35, -216.234) -> (47.7803, -216.104)
  line L8807 (31.5109, -215.723) -> (30.9634, -215.927)
  line L8808 (107.159, -205.81) -> (107.277, -205.237)
  line L8809 (41.2578, -208.905) -> (41.3803, -209.486)
  line L8810 (34.0223, -214.047) -> (34.453, -213.638)
  line L8811 (19.6222, -204.122) -> (19.8482, -203.583)
  line L8812 (41.495, -204.792) -> (41.3443, -205.366)
  line L8813 (42.8876, -212.689) -> (43.2572, -213.154)
  line L8814 (58.8551, -205.58) -> (58.7185, -205.002)
  line L8815 (43.5489, -201.22) -> (43.157, -201.666)
  line L8816 (21.2572, -213.154) -> (21.6569, -213.593)
  line L8817 (41.1742, -208.317) -> (41.2578, -208.905)
  line L8818 (59.0951, -208.107) -> (59.0274, -208.688)
  line L8819 (20.9746, -212.959) -> (20.6274, -212.489)
  line L8820 (19.4315, -204.674) -> (19.6222, -204.122)
  line L8821 (42.3113, -211.998) -> (42.0276, -211.487)
  line L8822 (117.43, -198.402) -> (118.005, -198.508)
  line L8823 (47.7803, -216.104) -> (47.2202, -215.937)
  line L8824 (35.8006, -202.818) -> (35.4833, -202.317)
  line L8825 (27.682, -198.309) -> (28.2663, -198.302)
  line L8826 (122.938, -201.449) -> (123.304, -201.904)
  line L8827 (41.9088, -203.679) -> (41.6834, -204.229)
  line L8828 (46.5778, -215.593) -> (47.1318, -215.807)
  line L8829 (111.772, -199.389) -> (112.295, -199.128)
  line L8830 (25.5484, -198.759) -> (24.9847, -198.946)
  line L8831 (29.075, -198.451) -> (28.483, -198.404)
  line L8832 (45.3845, -199.723) -> (44.8893, -200.051)
  line L8833 (19.2578, -208.905) -> (19.3803, -209.486)
  line L8834 (37.1251, -207.524) -> (37.0951, -208.107)
  line L8835 (116.266, -198.302) -> (116.85, -198.333)
  line L8836 (27.5085, -216.382) -> (26.9269, -216.327)
  line L8837 (42.6274, -212.489) -> (42.3113, -211.998)
  line L8838 (52.2432, -198.661) -> (51.6626, -198.537)
  line L8839 (33.9903, -214.201) -> (33.5358, -214.568)
  line L8840 (21.5489, -201.22) -> (21.157, -201.666)
  line L8841 (56.42, -213.805) -> (55.9903, -214.201)
  line L8842 (19.3443, -205.366) -> (19.232, -205.949)
  line L8843 (33.0844, -214.774) -> (33.5654, -214.426)
  line L8844 (58.9531, -206.166) -> (58.8551, -205.58)
  line L8845 (25.2202, -215.937) -> (24.672, -215.735)
  line L8846 (43.9695, -200.801) -> (43.5489, -201.22)
  line L8847 (59.0318, -207.35) -> (59.0121, -206.757)
  line L8848 (41.1297, -207.725) -> (41.1742, -208.317)
  line L8849 (24.4345, -199.169) -> (23.9003, -199.429)
  line L8850 (44.8893, -200.051) -> (44.417, -200.41)
  line L8851 (55.4411, -200.179) -> (54.954, -199.84)
  line L8852 (23.1214, -214.923) -> (22.643, -214.587)
  line L8853 (58.9575, -205.608) -> (59.0514, -206.184)
  line L8854 (57.5441, -212.463) -> (57.1986, -212.934)
  line L8855 (58.084, -203.34) -> (57.8006, -202.818)
  line L8856 (56.3423, -200.952) -> (55.9045, -200.551)
  line L8857 (31.5182, -215.617) -> (32.0585, -215.371)
  line L8858 (57.9457, -202.88) -> (58.2178, -203.397)
  line L8859 (46.138, -215.498) -> (45.6204, -215.227)
  line L8860 (36.8551, -205.58) -> (36.7185, -205.002)
  line L8861 (55.0587, -214.905) -> (54.5607, -215.211)
  line L8862 (45.5183, -215.058) -> (46.0392, -215.343)
  line L8863 (19.0347, -206.971) -> (19.078, -206.388)
  line L8864 (41.2321, -205.949) -> (41.1587, -206.538)
  line L8865 (19.0332, -207.131) -> (19.0347, -206.971)
  line L8866 (124.456, -203.931) -> (124.659, -204.478)
  line L8867 (34.9379, -201.449) -> (35.3045, -201.904)
  line L8868 (43.157, -201.666) -> (42.7955, -202.137)
  line L8869 (23.3845, -199.723) -> (22.8893, -200.051)
  line L8870 (58.7806, -209.829) -> (58.6024, -210.386)
  line L8871 (42.9746, -212.959) -> (42.6274, -212.489)
  line L8872 (54.4456, -199.533) -> (53.9179, -199.261)
  line L8873 (37.0121, -206.757) -> (36.9531, -206.166)
  line L8874 (32.5607, -215.211) -> (32.0441, -215.484)
  line L8875 (28.8498, -198.333) -> (29.4301, -198.402)
  line L8876 (28.483, -198.404) -> (27.8893, -198.397)
  line L8877 (59.0211, -207.787) -> (59.0318, -207.35)
  line L8878 (30.4039, -216.096) -> (29.8346, -216.228)
  line L8879 (52.8143, -198.824) -> (52.2432, -198.661)
  line L8880 (41.0347, -206.971) -> (41.078, -206.388)
  line L8881 (52.9634, -215.927) -> (52.4039, -216.096)
  line L8882 (48.9269, -216.327) -> (48.35, -216.234)
  line L8883 (26.2761, -216.122) -> (26.8615, -216.222)
  line L8884 (108.402, -202.554) -> (108.727, -202.069)
  line L8885 (41.1309, -208.719) -> (41.0612, -208.139)
  line L8886 (57.8785, -211.746) -> (58.1527, -211.219)
  line L8887 (20.3113, -211.998) -> (20.0276, -211.487)
  line L8888 (57.2286, -212.739) -> (57.57, -212.253)
  line L8889 (57.6409, -202.381) -> (57.9457, -202.88)
  line L8890 (22.1873, -214.221) -> (21.7561, -213.827)
  line L8891 (55.6734, -200.238) -> (56.1207, -200.614)
  line L8892 (50.6766, -216.38) -> (50.0926, -216.4)
  line L8893 (21.157, -201.666) -> (20.7955, -202.137)
  line L8894 (58.1527, -211.219) -> (58.3914, -210.676)
  line L8895 (124.827, -205.038) -> (124.957, -205.608)
  line L8896 (37.1079, -206.766) -> (37.1268, -207.35)
  line L8897 (59.0514, -206.184) -> (59.1079, -206.766)
  line L8898 (119.128, -198.83) -> (119.671, -199.044)
  line L8899 (50.6391, -216.287) -> (51.2302, -216.23)
  line L8900 (43.6569, -213.593) -> (44.0847, -214.005)
  line L8901 (19.0612, -208.139) -> (19.0291, -207.555)
  line L8902 (58.3887, -210.93) -> (58.1404, -211.459)
  line L8903 (23.0175, -214.739) -> (23.5183, -215.058)
  line L8904 (31.9179, -199.261) -> (31.3734, -199.024)
  line L8905 (53.5109, -215.723) -> (52.9634, -215.927)
  line L8906 (31.3734, -199.024) -> (30.8143, -198.824)
  line L8907 (36.8847, -208.967) -> (36.9725, -208.379)
  line L8908 (52.3945, -216) -> (52.9627, -215.827)
  line L8909 (34.1207, -200.614) -> (34.5428, -201.018)
  line L8910 (35.4833, -202.317) -> (35.1334, -201.837)
  line L8911 (26.8615, -216.222) -> (27.4521, -216.283)
  line L8912 (41.6834, -204.229) -> (41.495, -204.792)
  line L8913 (57.57, -212.253) -> (57.8785, -211.746)
  line L8914 (56.7525, -201.381) -> (56.3423, -200.952)
  line L8915 (19.1742, -208.317) -> (19.2578, -208.905)
  line L8916 (54.0441, -215.484) -> (53.5109, -215.723)
  line L8917 (44.417, -200.41) -> (43.9695, -200.801)
  line L8918 (56.5428, -201.018) -> (56.9379, -201.449)
  line L8919 (35.8785, -211.746) -> (36.1527, -211.219)
  line L8920 (30.0047, -198.508) -> (30.5713, -198.651)
  line L8921 (107.432, -204.674) -> (107.622, -204.122)
  line L8922 (59.1079, -206.766) -> (59.1268, -207.35)
  line L8923 (55.9045, -200.551) -> (55.4411, -200.179)
  line L8924 (34.8557, -213.201) -> (35.2286, -212.739)
  line L8925 (41.7392, -210.617) -> (41.9741, -211.163)
  line L8926 (58.6591, -204.478) -> (58.8266, -205.038)
  line L8927 (111.268, -199.684) -> (111.772, -199.389)
  line L8928 (35.5441, -212.463) -> (35.1986, -212.934)
  line L8929 (22.8893, -200.051) -> (22.417, -200.41)
  line L8930 (35.2286, -212.739) -> (35.57, -212.253)
  line L8931 (22.7829, -200.01) -> (23.2676, -199.684)
  line L8932 (25.9488, -198.554) -> (26.5208, -198.435)
  line L8933 (34.5428, -201.018) -> (34.9379, -201.449)
  line L8934 (37.0951, -208.107) -> (37.0274, -208.688)
  line L8935 (124.218, -203.397) -> (124.456, -203.931)
  line L8936 (24.672, -215.735) -> (24.138, -215.498)
  line L8937 (29.6626, -198.537) -> (29.075, -198.451)
  line L8938 (109.084, -201.606) -> (109.469, -201.166)
  line L8939 (36.5439, -204.435) -> (36.3321, -203.88)
  line L8940 (57.8585, -211.97) -> (57.5441, -212.463)
  line L8941 (46.0392, -215.343) -> (46.5778, -215.593)
  line L8942 (27.8893, -198.397) -> (27.2963, -198.429)
  line L8943 (28.6391, -216.287) -> (29.2302, -216.23)
  line L8944 (56.1207, -200.614) -> (56.5428, -201.018)
  line L8945 (26.9269, -216.327) -> (26.35, -216.234)
  line L8946 (33.4411, -200.179) -> (32.954, -199.84)
  line L8947 (36.2178, -203.397) -> (36.4559, -203.931)
  line L8948 (22.643, -214.587) -> (22.1873, -214.221)
  line L8949 (31.671, -199.044) -> (32.1995, -199.294)
  line L8950 (113.386, -198.709) -> (113.949, -198.554)
  line L8951 (51.8162, -216.134) -> (52.3945, -216)
  line L8952 (29.8346, -216.228) -> (29.2581, -216.323)
  line L8953 (58.9224, -209.262) -> (58.7806, -209.829)
  line L8954 (22.417, -200.41) -> (21.9695, -200.801)
  line L8955 (19.1309, -208.719) -> (19.0612, -208.139)
  line L8956 (36.1527, -211.219) -> (36.3914, -210.676)
  line L8957 (51.8346, -216.228) -> (51.2581, -216.323)
  line L8958 (58.2178, -203.397) -> (58.4559, -203.931)
  line L8959 (28.0926, -216.4) -> (27.5085, -216.382)
  line L8960 (32.7108, -199.576) -> (33.2028, -199.892)
  line L8961 (48.1233, -198.611) -> (47.5484, -198.759)
  line L8962 (42.17, -203.146) -> (41.9088, -203.679)
  line L8963 (19.8482, -203.583) -> (20.1085, -203.06)
  line L8964 (31.1275, -198.83) -> (31.671, -199.044)
  line L8965 (27.2963, -198.429) -> (26.7068, -198.5)
  line L8966 (41.541, -210.058) -> (41.7392, -210.617)
  line L8967 (107.848, -203.583) -> (108.108, -203.06)
  line L8968 (19.541, -210.058) -> (19.7392, -210.617)
  line L8969 (19.1589, -205.81) -> (19.2769, -205.237)
  line L8970 (45.1214, -214.923) -> (44.643, -214.587)
  line L8971 (20.5495, -212.201) -> (20.8876, -212.689)
  line L8972 (25.1318, -215.807) -> (25.6987, -215.983)
  line L8973 (32.5813, -215.09) -> (33.0844, -214.774)
  line L8974 (58.4559, -203.931) -> (58.6591, -204.478)
  line L8975 (19.5618, -210.416) -> (19.3817, -209.86)
  line L8976 (24.138, -215.498) -> (23.6204, -215.227)
  line L8977 (30.5713, -198.651) -> (31.1275, -198.83)
  line L8978 (36.3887, -210.93) -> (36.1404, -211.459)
  line L8979 (28.0455, -216.305) -> (28.6391, -216.287)
  line L8980 (42.0276, -211.487) -> (41.7774, -210.959)
  line L8981 (49.5085, -216.382) -> (48.9269, -216.327)
  line L8982 (58.6024, -210.386) -> (58.3887, -210.93)
  line L8983 (57.1986, -212.934) -> (56.8234, -213.382)
  line L8984 (109.882, -200.753) -> (110.32, -200.367)
  line L8985 (33.0587, -214.905) -> (32.5607, -215.211)
  line L8986 (20.7274, -202.069) -> (21.0836, -201.606)
  line L8987 (36.6591, -204.478) -> (36.8266, -205.038)
  line L8988 (46.672, -215.735) -> (46.138, -215.498)
  line L8989 (54.954, -199.84) -> (54.4456, -199.533)
  line L8990 (110.783, -200.01) -> (111.268, -199.684)
  line L8991 (19.1245, -207.131) -> (19.1297, -207.725)
  line L8992 (41.0291, -207.555) -> (41.0332, -207.131)
  line L8993 (19.1587, -206.538) -> (19.1245, -207.131)
  line L8994 (55.0844, -214.774) -> (55.5654, -214.426)
  line L8995 (19.9088, -203.679) -> (19.6834, -204.229)
  line L8996 (121.673, -200.238) -> (122.121, -200.614)
  line L8997 (37.0274, -208.688) -> (36.9224, -209.262)
  line L8998 (55.9903, -214.201) -> (55.5358, -214.568)
  line L8999 (21.0836, -201.606) -> (21.4688, -201.166)
  line L9000 (35.57, -212.253) -> (35.8785, -211.746)
  line L9001 (35.8585, -211.97) -> (35.5441, -212.463)
  line L9002 (56.0223, -214.047) -> (56.453, -213.638)
  line L9003 (36.7185, -205.002) -> (36.5439, -204.435)
  line L9004 (121.203, -199.892) -> (121.673, -200.238)
  line L9005 (32.0585, -215.371) -> (32.5813, -215.09)
  line L9006 (37.0514, -206.184) -> (37.1079, -206.766)
  line L9007 (34.8234, -213.382) -> (34.42, -213.805)
  line L9008 (51.2302, -216.23) -> (51.8162, -216.134)
  line L9009 (30.3945, -216) -> (30.9627, -215.827)